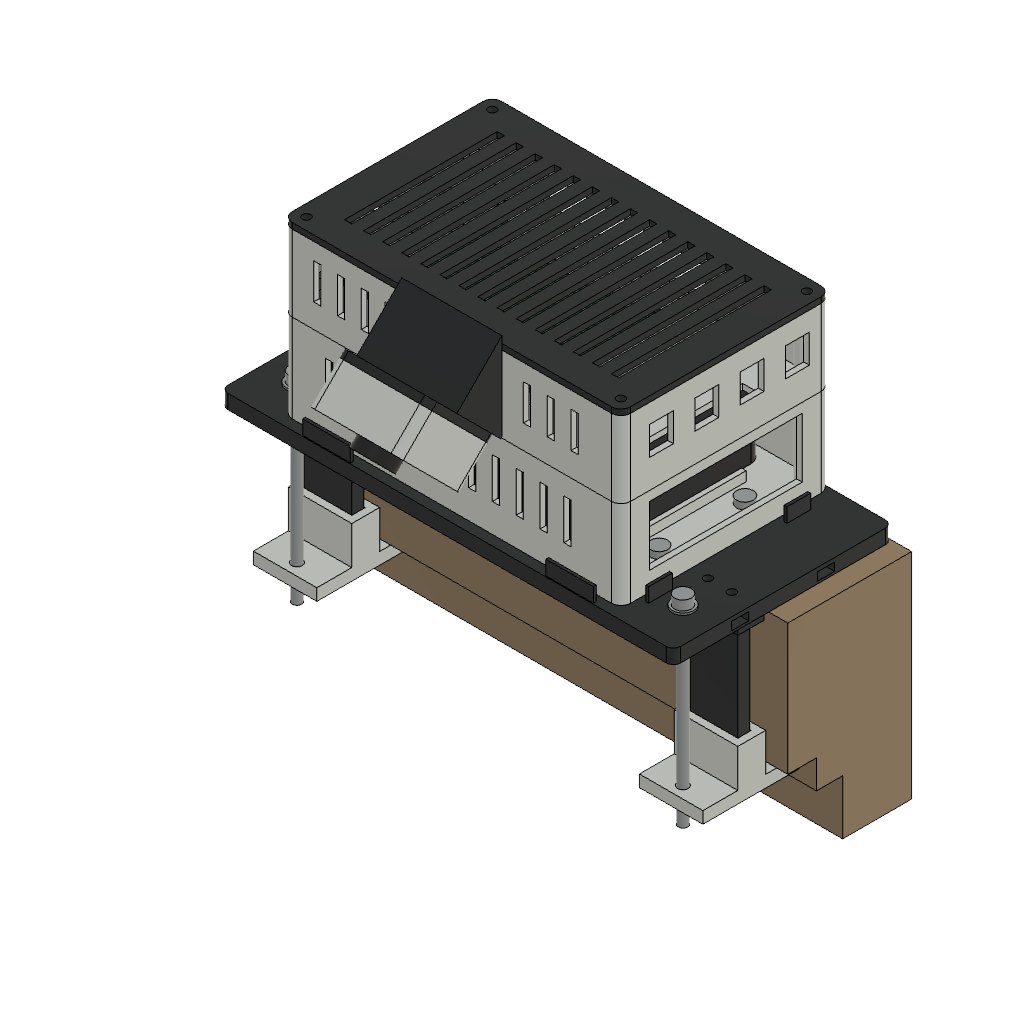
doorframe-camera-mounted-v3 (Autodesk Fusion 360 design; units mm, degrees)
part number: 2026-11-08-18-06-19-159
part number: 2026-11-08-18-06-19-927
part number: 2026-11-08-18-06-22-898
part number: 2026-11-08-18-06-26-282
part number: 2026-11-08-18-06-29-546
part number: 2026-11-08-18-06-30-123
part number: 2026-11-08-18-06-33-594
part number: 2026-11-08-18-06-36-129
part number: 2026-11-08-18-06-39-085
part number: 2026-11-08-18-06-42-850
part number: 2026-11-08-18-08-24-146
part number: 2026-11-08-20-22-30-806
part number: 2026-11-08-20-22-44-383
part number: 2026-11-08-20-22-46-977
part number: 2026-11-08-20-22-52-675
part number: 2026-11-08-20-22-55-258
part number: 2026-11-08-20-22-58-971
part number: 2026-11-08-20-22-59-876
part number: 2026-11-08-20-23-00-191
part number: 2026-11-08-20-26-10-020
Autodesk Fusion 360 part; units mm, degrees
(part 1 of 2)
sketch "Battery tray shell outline" plane through (0, 0, 0) normal (0, 0, 1) x (1, 0, 0) in component "01 Battery tray - PRINT"
  line L0 (4, 0) -> (138, 0)
  line L1 (142, 4) -> (142, 84)
  line L2 (138, 88) -> (4, 88)
  line L3 (0, 84) -> (0, 4)
  arc A0 (138, 0) -> (142, 4) centre (138, 4) ccw
  arc A1 (142, 84) -> (138, 88) centre (138, 84) ccw
  arc A2 (4, 88) -> (0, 84) centre (4, 84) ccw
  arc A3 (0, 4) -> (4, 0) centre (4, 4) ccw
extrude "Battery tray shell" add sketch "Battery tray shell outline" along normal blind 37 makes body 1 in component "01 Battery tray - PRINT"
ref_plane "WorkPlane1" through (0, 0, 2.4) normal (0, 0, 1) x (1, 0, 0) in component "01 Battery tray - PRINT"
sketch "Battery chamber outline" plane through (0, 0, 2.4) normal (0, 0, 1) x (1, 0, 0) in component "01 Battery tray - PRINT"
  line L0 (4, 2.4) -> (138, 2.4)
  line L1 (139.6, 4) -> (139.6, 84)
  line L2 (138, 85.6) -> (4, 85.6)
  line L3 (2.4, 84) -> (2.4, 4)
  arc A0 (138, 2.4) -> (139.6, 4) centre (138, 4) ccw
  arc A1 (139.6, 84) -> (138, 85.6) centre (138, 84) ccw
  arc A2 (4, 85.6) -> (2.4, 84) centre (4, 84) ccw
  arc A3 (2.4, 4) -> (4, 2.4) centre (4, 4) ccw
extrude "Battery chamber" cut sketch "Battery chamber outline" along normal blind 37 bodies 1 in component "01 Battery tray - PRINT"
ref_plane "WorkPlane2" through (0, 0, 2.4) normal (0, 0, 1) x (1, 0, 0) in component "01 Battery tray - PRINT"
sketch "Four corner screw pillars layout" plane through (0, 0, 2.4) normal (0, 0, 1) x (1, 0, 0) in component "01 Battery tray - PRINT"
  circle A0 centre (5, 5) radius 4
  circle A1 centre (137, 5) radius 4
  circle A2 centre (5, 83) radius 4
  circle A3 centre (137, 83) radius 4
extrude "Four corner screw pillars" add sketch "Four corner screw pillars layout" along normal blind 34.6 bodies 1 in component "01 Battery tray - PRINT"
ref_plane "WorkPlane3" through (0, 0, 22) normal (0, 0, 1) x (1, 0, 0) in component "01 Battery tray - PRINT"
sketch "M3 pilot holes - hand tap or plastic screws layout" plane through (0, 0, 22) normal (0, 0, 1) x (1, 0, 0) in component "01 Battery tray - PRINT"
  circle A0 centre (5, 5) radius 1.25
  circle A1 centre (137, 5) radius 1.25
  circle A2 centre (5, 83) radius 1.25
  circle A3 centre (137, 83) radius 1.25
extrude "M3 pilot holes - hand tap or plastic screws" cut sketch "M3 pilot holes - hand tap or plastic screws layout" along normal blind 16 bodies 1 in component "01 Battery tray - PRINT"
sketch "Battery strap slots - two 10 mm straps layout" plane through (0, 0, 0) normal (0, 0, 1) x (1, 0, 0) in component "01 Battery tray - PRINT"
  line L0 (41, 4) -> (53, 4)
  line L1 (53, 4) -> (53, 6.2)
  line L2 (53, 6.2) -> (41, 6.2)
  line L3 (41, 6.2) -> (41, 4)
  line L4 (41, 81.8) -> (53, 81.8)
  line L5 (53, 81.8) -> (53, 84)
  line L6 (53, 84) -> (41, 84)
  line L7 (41, 84) -> (41, 81.8)
  line L8 (94, 4) -> (106, 4)
  line L9 (106, 4) -> (106, 6.2)
  line L10 (106, 6.2) -> (94, 6.2)
  line L11 (94, 6.2) -> (94, 4)
  line L12 (94, 81.8) -> (106, 81.8)
  line L13 (106, 81.8) -> (106, 84)
  line L14 (106, 84) -> (94, 84)
  line L15 (94, 84) -> (94, 81.8)
extrude "Battery strap slots - two 10 mm straps" cut sketch "Battery strap slots - two 10 mm straps layout" along normal blind 3 bodies 1 in component "01 Battery tray - PRINT"
sketch "Rubber pad pockets - 20 x 10 mm layout" plane through (0, 0, 0) normal (0, 0, 1) x (1, 0, 0) in component "01 Battery tray - PRINT"
  line L0 (12, 7) -> (32, 7)
  line L1 (32, 7) -> (32, 17)
  line L2 (32, 17) -> (12, 17)
  line L3 (12, 17) -> (12, 7)
  line L4 (110, 7) -> (130, 7)
  line L5 (130, 7) -> (130, 17)
  line L6 (130, 17) -> (110, 17)
  line L7 (110, 17) -> (110, 7)
  line L8 (12, 71) -> (32, 71)
  line L9 (32, 71) -> (32, 81)
  line L10 (32, 81) -> (12, 81)
  line L11 (12, 81) -> (12, 71)
  line L12 (110, 71) -> (130, 71)
  line L13 (130, 71) -> (130, 81)
  line L14 (130, 81) -> (110, 81)
  line L15 (110, 81) -> (110, 71)
extrude "Rubber pad pockets - 20 x 10 mm" cut sketch "Rubber pad pockets - 20 x 10 mm layout" along normal blind 0.8 bodies 1 in component "01 Battery tray - PRINT"
ref_plane "WorkPlane4" through (0, 0, 12) normal (0, 0, 1) x (1, 0, 0) in component "01 Battery tray - PRINT"
sketch "Battery air slots layout" plane through (0, 0, 12) normal (0, 0, 1) x (1, 0, 0) in component "01 Battery tray - PRINT"
  line L0 (18, -1) -> (21, -1)
  line L1 (21, -1) -> (21, 3.2)
  line L2 (21, 3.2) -> (18, 3.2)
  line L3 (18, 3.2) -> (18, -1)
  line L4 (28, -1) -> (31, -1)
  line L5 (31, -1) -> (31, 3.2)
  line L6 (31, 3.2) -> (28, 3.2)
  line L7 (28, 3.2) -> (28, -1)
  line L8 (38, -1) -> (41, -1)
  line L9 (41, -1) -> (41, 3.2)
  line L10 (41, 3.2) -> (38, 3.2)
  line L11 (38, 3.2) -> (38, -1)
  line L12 (48, -1) -> (51, -1)
  line L13 (51, -1) -> (51, 3.2)
  line L14 (51, 3.2) -> (48, 3.2)
  line L15 (48, 3.2) -> (48, -1)
  line L16 (58, -1) -> (61, -1)
  line L17 (61, -1) -> (61, 3.2)
  line L18 (61, 3.2) -> (58, 3.2)
  line L19 (58, 3.2) -> (58, -1)
  line L20 (68, -1) -> (71, -1)
  line L21 (71, -1) -> (71, 3.2)
  line L22 (71, 3.2) -> (68, 3.2)
  line L23 (68, 3.2) -> (68, -1)
  line L24 (78, -1) -> (81, -1)
  line L25 (81, -1) -> (81, 3.2)
  line L26 (81, 3.2) -> (78, 3.2)
  line L27 (78, 3.2) -> (78, -1)
  line L28 (88, -1) -> (91, -1)
  line L29 (91, -1) -> (91, 3.2)
  line L30 (91, 3.2) -> (88, 3.2)
  line L31 (88, 3.2) -> (88, -1)
  line L32 (98, -1) -> (101, -1)
  line L33 (101, -1) -> (101, 3.2)
  line L34 (101, 3.2) -> (98, 3.2)
  line L35 (98, 3.2) -> (98, -1)
  line L36 (108, -1) -> (111, -1)
  line L37 (111, -1) -> (111, 3.2)
  line L38 (111, 3.2) -> (108, 3.2)
  line L39 (108, 3.2) -> (108, -1)
  line L40 (118, -1) -> (121, -1)
  line L41 (121, -1) -> (121, 3.2)
  line L42 (121, 3.2) -> (118, 3.2)
  line L43 (118, 3.2) -> (118, -1)
  line L44 (18, 84.8) -> (21, 84.8)
  line L45 (21, 84.8) -> (21, 89)
  line L46 (21, 89) -> (18, 89)
  line L47 (18, 89) -> (18, 84.8)
  line L48 (28, 84.8) -> (31, 84.8)
  line L49 (31, 84.8) -> (31, 89)
  line L50 (31, 89) -> (28, 89)
  line L51 (28, 89) -> (28, 84.8)
  line L52 (38, 84.8) -> (41, 84.8)
  line L53 (41, 84.8) -> (41, 89)
  line L54 (41, 89) -> (38, 89)
  line L55 (38, 89) -> (38, 84.8)
  line L56 (48, 84.8) -> (51, 84.8)
  line L57 (51, 84.8) -> (51, 89)
  line L58 (51, 89) -> (48, 89)
  line L59 (48, 89) -> (48, 84.8)
  line L60 (58, 84.8) -> (61, 84.8)
  line L61 (61, 84.8) -> (61, 89)
  line L62 (61, 89) -> (58, 89)
  line L63 (58, 89) -> (58, 84.8)
  line L64 (68, 84.8) -> (71, 84.8)
  line L65 (71, 84.8) -> (71, 89)
  line L66 (71, 89) -> (68, 89)
  line L67 (68, 89) -> (68, 84.8)
  line L68 (78, 84.8) -> (81, 84.8)
  line L69 (81, 84.8) -> (81, 89)
  line L70 (81, 89) -> (78, 89)
  line L71 (78, 89) -> (78, 84.8)
  line L72 (88, 84.8) -> (91, 84.8)
  line L73 (91, 84.8) -> (91, 89)
  line L74 (91, 89) -> (88, 89)
  line L75 (88, 89) -> (88, 84.8)
  line L76 (98, 84.8) -> (101, 84.8)
  line L77 (101, 84.8) -> (101, 89)
  line L78 (101, 89) -> (98, 89)
  line L79 (98, 89) -> (98, 84.8)
  line L80 (108, 84.8) -> (111, 84.8)
  line L81 (111, 84.8) -> (111, 89)
  line L82 (111, 89) -> (108, 89)
  line L83 (108, 89) -> (108, 84.8)
  line L84 (118, 84.8) -> (121, 84.8)
  line L85 (121, 84.8) -> (121, 89)
  line L86 (121, 89) -> (118, 89)
  line L87 (118, 89) -> (118, 84.8)
extrude "Battery air slots" cut sketch "Battery air slots layout" along normal blind 17 bodies 1 in component "01 Battery tray - PRINT"
ref_plane "WorkPlane5" through (0, 0, 8) normal (0, 0, 1) x (1, 0, 0) in component "01 Battery tray - PRINT"
sketch "Battery connector access layout" plane through (0, 0, 8) normal (0, 0, 1) x (1, 0, 0) in component "01 Battery tray - PRINT"
  line L0 (139, 12) -> (143, 12)
  line L1 (143, 12) -> (143, 76)
  line L2 (143, 76) -> (139, 76)
  line L3 (139, 76) -> (139, 12)
extrude "Battery connector access" cut sketch "Battery connector access layout" along normal blind 25 bodies 1 in component "01 Battery tray - PRINT"
ref_plane "WorkPlane6" through (0, 0, 2.4) normal (0, 0, 1) x (1, 0, 0) in component "01 Battery tray - PRINT"
sketch "Battery end stop outline" plane through (0, 0, 2.4) normal (0, 0, 1) x (1, 0, 0) in component "01 Battery tray - PRINT"
  line L0 (3, 18) -> (5, 18)
  line L1 (5, 18) -> (5, 70)
  line L2 (5, 70) -> (3, 70)
  line L3 (3, 70) -> (3, 18)
extrude "Battery end stop" add sketch "Battery end stop outline" along normal blind 4 bodies 1 in component "01 Battery tray - PRINT"
ref_plane "WorkPlane7" through (0, 0, 2.4) normal (0, 0, 1) x (1, 0, 0) in component "01 Battery tray - PRINT"
sketch "Battery cable-side stop outline" plane through (0, 0, 2.4) normal (0, 0, 1) x (1, 0, 0) in component "01 Battery tray - PRINT"
  line L0 (122.5, 18) -> (124.5, 18)
  line L1 (124.5, 18) -> (124.5, 70)
  line L2 (124.5, 70) -> (122.5, 70)
  line L3 (122.5, 70) -> (122.5, 18)
extrude "Battery cable-side stop" add sketch "Battery cable-side stop outline" along normal blind 4 bodies 1 in component "01 Battery tray - PRINT"
sketch "M4 mounting interface layout" plane through (0, 0, 0) normal (0, 0, 1) x (1, 0, 0) in component "01 Battery tray - PRINT"
  circle A0 centre (132, 26) radius 2.25
  circle A1 centre (132, 62) radius 2.25
extrude "M4 mounting interface" cut sketch "M4 mounting interface layout" along normal blind 3 bodies 1 in component "01 Battery tray - PRINT"
ref_plane "WorkPlane1" through (0, 0, 37) normal (0, 0, 1) x (1, 0, 0) in component "02 Pi tray and upper shell - PRINT"
sketch "Upper shell outline" plane through (0, 0, 37) normal (0, 0, 1) x (1, 0, 0) in component "02 Pi tray and upper shell - PRINT"
  line L0 (4, 0) -> (138, 0)
  line L1 (142, 4) -> (142, 84)
  line L2 (138, 88) -> (4, 88)
  line L3 (0, 84) -> (0, 4)
  arc A0 (138, 0) -> (142, 4) centre (138, 4) ccw
  arc A1 (142, 84) -> (138, 88) centre (138, 84) ccw
  arc A2 (4, 88) -> (0, 84) centre (4, 84) ccw
  arc A3 (0, 4) -> (4, 0) centre (4, 4) ccw
extrude "Upper shell" add sketch "Upper shell outline" along normal blind 32 separate body makes body 2 in component "02 Pi tray and upper shell - PRINT"
ref_plane "WorkPlane2" through (0, 0, 39.4) normal (0, 0, 1) x (1, 0, 0) in component "02 Pi tray and upper shell - PRINT"
sketch "Pi chamber outline" plane through (0, 0, 39.4) normal (0, 0, 1) x (1, 0, 0) in component "02 Pi tray and upper shell - PRINT"
  line L0 (4, 2.4) -> (138, 2.4)
  line L1 (139.6, 4) -> (139.6, 84)
  line L2 (138, 85.6) -> (4, 85.6)
  line L3 (2.4, 84) -> (2.4, 4)
  arc A0 (138, 2.4) -> (139.6, 4) centre (138, 4) ccw
  arc A1 (139.6, 84) -> (138, 85.6) centre (138, 84) ccw
  arc A2 (4, 85.6) -> (2.4, 84) centre (4, 84) ccw
  arc A3 (2.4, 4) -> (4, 2.4) centre (4, 4) ccw
extrude "Pi chamber" cut sketch "Pi chamber outline" along normal blind 32 bodies 2 in component "02 Pi tray and upper shell - PRINT"
ref_plane "WorkPlane3" through (0, 0, 39.4) normal (0, 0, 1) x (1, 0, 0) in component "02 Pi tray and upper shell - PRINT"
sketch "Upper corner pillars layout" plane through (0, 0, 39.4) normal (0, 0, 1) x (1, 0, 0) in component "02 Pi tray and upper shell - PRINT"
  circle A0 centre (5, 5) radius 4
  circle A1 centre (137, 5) radius 4
  circle A2 centre (5, 83) radius 4
  circle A3 centre (137, 83) radius 4
extrude "Upper corner pillars" add sketch "Upper corner pillars layout" along normal blind 29.6 bodies 2 in component "02 Pi tray and upper shell - PRINT"
ref_plane "WorkPlane4" through (0, 0, 36.8) normal (0, 0, 1) x (1, 0, 0) in component "02 Pi tray and upper shell - PRINT"
sketch "M3 long-screw clearance layout" plane through (0, 0, 36.8) normal (0, 0, 1) x (1, 0, 0) in component "02 Pi tray and upper shell - PRINT"
  circle A0 centre (5, 5) radius 1.7
  circle A1 centre (137, 5) radius 1.7
  circle A2 centre (5, 83) radius 1.7
  circle A3 centre (137, 83) radius 1.7
extrude "M3 long-screw clearance" cut sketch "M3 long-screw clearance layout" along normal blind 33 bodies 2 in component "02 Pi tray and upper shell - PRINT"
ref_plane "WorkPlane5" through (0, 0, 39.4) normal (0, 0, 1) x (1, 0, 0) in component "02 Pi tray and upper shell - PRINT"
sketch "Pi4 mounting standoffs - 58 x 49 mm layout" plane through (0, 0, 39.4) normal (0, 0, 1) x (1, 0, 0) in component "02 Pi tray and upper shell - PRINT"
  circle A0 centre (87.5, 67.5) radius 3
  circle A1 centre (29.5, 67.5) radius 3
  circle A2 centre (87.5, 18.5) radius 3
  circle A3 centre (29.5, 18.5) radius 3
extrude "Pi4 mounting standoffs - 58 x 49 mm" add sketch "Pi4 mounting standoffs - 58 x 49 mm layout" along normal blind 5 bodies 2 in component "02 Pi tray and upper shell - PRINT"
ref_plane "WorkPlane6" through (0, 0, 38) normal (0, 0, 1) x (1, 0, 0) in component "02 Pi tray and upper shell - PRINT"
sketch "M2.5 Pi screw pilot holes layout" plane through (0, 0, 38) normal (0, 0, 1) x (1, 0, 0) in component "02 Pi tray and upper shell - PRINT"
  circle A0 centre (87.5, 67.5) radius 1.05
  circle A1 centre (29.5, 67.5) radius 1.05
  circle A2 centre (87.5, 18.5) radius 1.05
  circle A3 centre (29.5, 18.5) radius 1.05
extrude "M2.5 Pi screw pilot holes" cut sketch "M2.5 Pi screw pilot holes layout" along normal blind 7.4 bodies 2 in component "02 Pi tray and upper shell - PRINT"
ref_plane "WorkPlane7" through (0, 0, 43.6) normal (0, 0, 1) x (1, 0, 0) in component "02 Pi tray and upper shell - PRINT"
sketch "USB and Ethernet access layout" plane through (0, 0, 43.6) normal (0, 0, 1) x (1, 0, 0) in component "02 Pi tray and upper shell - PRINT"
  line L0 (-1, 12) -> (3.2, 12)
  line L1 (3.2, 12) -> (3.2, 76)
  line L2 (3.2, 76) -> (-1, 76)
  line L3 (-1, 76) -> (-1, 12)
extrude "USB and Ethernet access" cut sketch "USB and Ethernet access layout" along normal blind 20 bodies 2 in component "02 Pi tray and upper shell - PRINT"
ref_plane "WorkPlane8" through (0, 0, 43.5) normal (0, 0, 1) x (1, 0, 0) in component "02 Pi tray and upper shell - PRINT"
sketch "USB-C and micro-HDMI access layout" plane through (0, 0, 43.5) normal (0, 0, 1) x (1, 0, 0) in component "02 Pi tray and upper shell - PRINT"
  line L0 (24, 84.8) -> (92, 84.8)
  line L1 (92, 84.8) -> (92, 89)
  line L2 (92, 89) -> (24, 89)
  line L3 (24, 89) -> (24, 84.8)
extrude "USB-C and micro-HDMI access" cut sketch "USB-C and micro-HDMI access layout" along normal blind 13 bodies 2 in component "02 Pi tray and upper shell - PRINT"
ref_plane "WorkPlane9" through (0, 0, 36.9) normal (0, 0, 1) x (1, 0, 0) in component "02 Pi tray and upper shell - PRINT"
sketch "Power and ribbon cable passage layout" plane through (0, 0, 36.9) normal (0, 0, 1) x (1, 0, 0) in component "02 Pi tray and upper shell - PRINT"
  line L0 (125, 20) -> (135, 20)
  line L1 (135, 20) -> (135, 68)
  line L2 (135, 68) -> (125, 68)
  line L3 (125, 68) -> (125, 20)
extrude "Power and ribbon cable passage" cut sketch "Power and ribbon cable passage layout" along normal blind 3 bodies 2 in component "02 Pi tray and upper shell - PRINT"
ref_plane "WorkPlane10" through (0, 0, 47) normal (0, 0, 1) x (1, 0, 0) in component "02 Pi tray and upper shell - PRINT"
sketch "Ventilation front layout" plane through (0, 0, 47) normal (0, 0, 1) x (1, 0, 0) in component "02 Pi tray and upper shell - PRINT"
  line L0 (13, -1) -> (16, -1)
  line L1 (16, -1) -> (16, 3.2)
  line L2 (16, 3.2) -> (13, 3.2)
  line L3 (13, 3.2) -> (13, -1)
  line L4 (23, -1) -> (26, -1)
  line L5 (26, -1) -> (26, 3.2)
  line L6 (26, 3.2) -> (23, 3.2)
  line L7 (23, 3.2) -> (23, -1)
  line L8 (33, -1) -> (36, -1)
  line L9 (36, -1) -> (36, 3.2)
  line L10 (36, 3.2) -> (33, 3.2)
  line L11 (33, 3.2) -> (33, -1)
  line L12 (43, -1) -> (46, -1)
  line L13 (46, -1) -> (46, 3.2)
  line L14 (46, 3.2) -> (43, 3.2)
  line L15 (43, 3.2) -> (43, -1)
  line L16 (101, -1) -> (104, -1)
  line L17 (104, -1) -> (104, 3.2)
  line L18 (104, 3.2) -> (101, 3.2)
  line L19 (101, 3.2) -> (101, -1)
  line L20 (111, -1) -> (114, -1)
  line L21 (114, -1) -> (114, 3.2)
  line L22 (114, 3.2) -> (111, 3.2)
  line L23 (111, 3.2) -> (111, -1)
  line L24 (121, -1) -> (124, -1)
  line L25 (124, -1) -> (124, 3.2)
  line L26 (124, 3.2) -> (121, 3.2)
  line L27 (121, 3.2) -> (121, -1)
extrude "Ventilation front" cut sketch "Ventilation front layout" along normal blind 15 bodies 2 in component "02 Pi tray and upper shell - PRINT"
ref_plane "WorkPlane11" through (0, 0, 49) normal (0, 0, 1) x (1, 0, 0) in component "02 Pi tray and upper shell - PRINT"
sketch "Ventilation right layout" plane through (0, 0, 49) normal (0, 0, 1) x (1, 0, 0) in component "02 Pi tray and upper shell - PRINT"
  line L0 (139, 12) -> (143, 12)
  line L1 (143, 12) -> (143, 22)
  line L2 (143, 22) -> (139, 22)
  line L3 (139, 22) -> (139, 12)
  line L4 (139, 31) -> (143, 31)
  line L5 (143, 31) -> (143, 41)
  line L6 (143, 41) -> (139, 41)
  line L7 (139, 41) -> (139, 31)
  line L8 (139, 50) -> (143, 50)
  line L9 (143, 50) -> (143, 60)
  line L10 (143, 60) -> (139, 60)
  line L11 (139, 60) -> (139, 50)
  line L12 (139, 69) -> (143, 69)
  line L13 (143, 69) -> (143, 79)
  line L14 (143, 79) -> (139, 79)
  line L15 (139, 79) -> (139, 69)
extrude "Ventilation right" cut sketch "Ventilation right layout" along normal blind 12 bodies 2 in component "02 Pi tray and upper shell - PRINT"
sketch "Camera bracket M3 clearance layout" plane through (0, 0, 0) normal (0, 1, 0) x (1, 0, 0) in component "02 Pi tray and upper shell - PRINT"
  circle A0 centre (59, -49) radius 1.7
  circle A1 centre (83, -49) radius 1.7
  circle A2 centre (59, -61) radius 1.7
  circle A3 centre (83, -61) radius 1.7
extrude "Camera bracket M3 clearance" cut sketch "Camera bracket M3 clearance layout" along normal blind 3 bodies 2 in component "02 Pi tray and upper shell - PRINT"
ref_plane "WorkPlane1" through (0, 0, 69) normal (0, 0, 1) x (1, 0, 0) in component "03 Vented lid - PRINT"
sketch "Lid outline" plane through (0, 0, 69) normal (0, 0, 1) x (1, 0, 0) in component "03 Vented lid - PRINT"
  line L0 (4, 0) -> (138, 0)
  line L1 (142, 4) -> (142, 84)
  line L2 (138, 88) -> (4, 88)
  line L3 (0, 84) -> (0, 4)
  arc A0 (138, 0) -> (142, 4) centre (138, 4) ccw
  arc A1 (142, 84) -> (138, 88) centre (138, 84) ccw
  arc A2 (4, 88) -> (0, 84) centre (4, 84) ccw
  arc A3 (0, 4) -> (4, 0) centre (4, 4) ccw
extrude "Lid" add sketch "Lid outline" along normal blind 2.4 separate body makes body 3 in component "03 Vented lid - PRINT"
ref_plane "WorkPlane2" through (0, 0, 68.9) normal (0, 0, 1) x (1, 0, 0) in component "03 Vented lid - PRINT"
sketch "M3 lid clearance layout" plane through (0, 0, 68.9) normal (0, 0, 1) x (1, 0, 0) in component "03 Vented lid - PRINT"
  circle A0 centre (5, 5) radius 1.7
  circle A1 centre (137, 5) radius 1.7
  circle A2 centre (5, 83) radius 1.7
  circle A3 centre (137, 83) radius 1.7
extrude "M3 lid clearance" cut sketch "M3 lid clearance layout" along normal blind 3 bodies 3 in component "03 Vented lid - PRINT"
ref_plane "WorkPlane3" through (0, 0, 68.9) normal (0, 0, 1) x (1, 0, 0) in component "03 Vented lid - PRINT"
sketch "Lid ventilation layout" plane through (0, 0, 68.9) normal (0, 0, 1) x (1, 0, 0) in component "03 Vented lid - PRINT"
  line L0 (14, 12) -> (17, 12)
  line L1 (17, 12) -> (17, 76)
  line L2 (17, 76) -> (14, 76)
  line L3 (14, 76) -> (14, 12)
  line L4 (22, 12) -> (25, 12)
  line L5 (25, 12) -> (25, 76)
  line L6 (25, 76) -> (22, 76)
  line L7 (22, 76) -> (22, 12)
  line L8 (30, 12) -> (33, 12)
  line L9 (33, 12) -> (33, 76)
  line L10 (33, 76) -> (30, 76)
  line L11 (30, 76) -> (30, 12)
  line L12 (38, 12) -> (41, 12)
  line L13 (41, 12) -> (41, 76)
  line L14 (41, 76) -> (38, 76)
  line L15 (38, 76) -> (38, 12)
  line L16 (46, 12) -> (49, 12)
  line L17 (49, 12) -> (49, 76)
  line L18 (49, 76) -> (46, 76)
  line L19 (46, 76) -> (46, 12)
  line L20 (54, 12) -> (57, 12)
  line L21 (57, 12) -> (57, 76)
  line L22 (57, 76) -> (54, 76)
  line L23 (54, 76) -> (54, 12)
  line L24 (62, 12) -> (65, 12)
  line L25 (65, 12) -> (65, 76)
  line L26 (65, 76) -> (62, 76)
  line L27 (62, 76) -> (62, 12)
  line L28 (70, 12) -> (73, 12)
  line L29 (73, 12) -> (73, 76)
  line L30 (73, 76) -> (70, 76)
  line L31 (70, 76) -> (70, 12)
  line L32 (78, 12) -> (81, 12)
  line L33 (81, 12) -> (81, 76)
  line L34 (81, 76) -> (78, 76)
  line L35 (78, 76) -> (78, 12)
  line L36 (86, 12) -> (89, 12)
  line L37 (89, 12) -> (89, 76)
  line L38 (89, 76) -> (86, 76)
  line L39 (86, 76) -> (86, 12)
  line L40 (94, 12) -> (97, 12)
  line L41 (97, 12) -> (97, 76)
  line L42 (97, 76) -> (94, 76)
  line L43 (94, 76) -> (94, 12)
  line L44 (102, 12) -> (105, 12)
  line L45 (105, 12) -> (105, 76)
  line L46 (105, 76) -> (102, 76)
  line L47 (102, 76) -> (102, 12)
  line L48 (110, 12) -> (113, 12)
  line L49 (113, 12) -> (113, 76)
  line L50 (113, 76) -> (110, 76)
  line L51 (110, 76) -> (110, 12)
  line L52 (118, 12) -> (121, 12)
  line L53 (121, 12) -> (121, 76)
  line L54 (121, 76) -> (118, 76)
  line L55 (118, 76) -> (118, 12)
  line L56 (126, 12) -> (129, 12)
  line L57 (129, 12) -> (129, 76)
  line L58 (129, 76) -> (126, 76)
  line L59 (126, 76) -> (126, 12)
extrude "Lid ventilation" cut sketch "Lid ventilation layout" along normal blind 3 bodies 3 in component "03 Vented lid - PRINT"
ref_plane "WorkPlane4" through (0, 0, 66.5) normal (0, 0, 1) x (1, 0, 0) in component "03 Vented lid - PRINT"
sketch "Lid alignment tab 1 outline" plane through (0, 0, 66.5) normal (0, 0, 1) x (1, 0, 0) in component "03 Vented lid - PRINT"
  line L0 (15, 2.8) -> (30, 2.8)
  line L1 (30, 2.8) -> (30, 4)
  line L2 (30, 4) -> (15, 4)
  line L3 (15, 4) -> (15, 2.8)
extrude "Lid alignment tab 1" add sketch "Lid alignment tab 1 outline" along normal blind 2.5 bodies 3 in component "03 Vented lid - PRINT"
ref_plane "WorkPlane5" through (0, 0, 66.5) normal (0, 0, 1) x (1, 0, 0) in component "03 Vented lid - PRINT"
sketch "Lid alignment tab 2 outline" plane through (0, 0, 66.5) normal (0, 0, 1) x (1, 0, 0) in component "03 Vented lid - PRINT"
  line L0 (111, 2.8) -> (126, 2.8)
  line L1 (126, 2.8) -> (126, 4)
  line L2 (126, 4) -> (111, 4)
  line L3 (111, 4) -> (111, 2.8)
extrude "Lid alignment tab 2" add sketch "Lid alignment tab 2 outline" along normal blind 2.5 bodies 3 in component "03 Vented lid - PRINT"
ref_plane "WorkPlane6" through (0, 0, 66.5) normal (0, 0, 1) x (1, 0, 0) in component "03 Vented lid - PRINT"
sketch "Lid alignment tab 3 outline" plane through (0, 0, 66.5) normal (0, 0, 1) x (1, 0, 0) in component "03 Vented lid - PRINT"
  line L0 (15, 84) -> (30, 84)
  line L1 (30, 84) -> (30, 85.2)
  line L2 (30, 85.2) -> (15, 85.2)
  line L3 (15, 85.2) -> (15, 84)
extrude "Lid alignment tab 3" add sketch "Lid alignment tab 3 outline" along normal blind 2.5 bodies 3 in component "03 Vented lid - PRINT"
ref_plane "WorkPlane7" through (0, 0, 66.5) normal (0, 0, 1) x (1, 0, 0) in component "03 Vented lid - PRINT"
sketch "Lid alignment tab 4 outline" plane through (0, 0, 66.5) normal (0, 0, 1) x (1, 0, 0) in component "03 Vented lid - PRINT"
  line L0 (111, 84) -> (126, 84)
  line L1 (126, 84) -> (126, 85.2)
  line L2 (126, 85.2) -> (111, 85.2)
  line L3 (111, 85.2) -> (111, 84)
extrude "Lid alignment tab 4" add sketch "Lid alignment tab 4 outline" along normal blind 2.5 bodies 3 in component "03 Vented lid - PRINT"
ref_plane "WorkPlane1" through (0, 0, 4.4) normal (0, 0, 1) x (1, 0, 0) in component "REFERENCE - INIU P51L-E2 115 x 73 x 29 mm"
sketch "INIU envelope - check supplied cable position outline" plane through (0, 0, 4.4) normal (0, 0, 1) x (1, 0, 0) in component "REFERENCE - INIU P51L-E2 115 x 73 x 29 mm"
  line L0 (11, 7.5) -> (116, 7.5)
  line L1 (121, 12.5) -> (121, 75.5)
  line L2 (116, 80.5) -> (11, 80.5)
  line L3 (6, 75.5) -> (6, 12.5)
  arc A0 (116, 7.5) -> (121, 12.5) centre (116, 12.5) ccw
  arc A1 (121, 75.5) -> (116, 80.5) centre (116, 75.5) ccw
  arc A2 (11, 80.5) -> (6, 75.5) centre (11, 75.5) ccw
  arc A3 (6, 12.5) -> (11, 7.5) centre (11, 12.5) ccw
extrude "INIU envelope - check supplied cable position" add sketch "INIU envelope - check supplied cable position outline" along normal blind 29 separate body makes body 4 in component "REFERENCE - INIU P51L-E2 115 x 73 x 29 mm"
ref_plane "WorkPlane1" through (0, 0, 44.4) normal (0, 0, 1) x (1, 0, 0) in component "REFERENCE - Raspberry Pi4 rotated ports"
sketch "Pi PCB 85 x 56 x 1.6 outline" plane through (0, 0, 44.4) normal (0, 0, 1) x (1, 0, 0) in component "REFERENCE - Raspberry Pi4 rotated ports"
  line L0 (9, 15) -> (88, 15)
  line L1 (91, 18) -> (91, 68)
  line L2 (88, 71) -> (9, 71)
  line L3 (6, 68) -> (6, 18)
  arc A0 (88, 15) -> (91, 18) centre (88, 18) ccw
  arc A1 (91, 68) -> (88, 71) centre (88, 68) ccw
  arc A2 (9, 71) -> (6, 68) centre (9, 68) ccw
  arc A3 (6, 18) -> (9, 15) centre (9, 18) ccw
extrude "Pi PCB 85 x 56 x 1.6" add sketch "Pi PCB 85 x 56 x 1.6 outline" along normal blind 1.6 separate body makes body 5 in component "REFERENCE - Raspberry Pi4 rotated ports"
ref_plane "WorkPlane2" through (0, 0, 44.3) normal (0, 0, 1) x (1, 0, 0) in component "REFERENCE - Raspberry Pi4 rotated ports"
sketch "Pi mounting holes layout" plane through (0, 0, 44.3) normal (0, 0, 1) x (1, 0, 0) in component "REFERENCE - Raspberry Pi4 rotated ports"
  circle A0 centre (87.5, 67.5) radius 1.375
  circle A1 centre (29.5, 67.5) radius 1.375
  circle A2 centre (87.5, 18.5) radius 1.375
  circle A3 centre (29.5, 18.5) radius 1.375
extrude "Pi mounting holes" cut sketch "Pi mounting holes layout" along normal blind 2 bodies 5 in component "REFERENCE - Raspberry Pi4 rotated ports"
ref_plane "WorkPlane3" through (0, 0, 46) normal (0, 0, 1) x (1, 0, 0) in component "REFERENCE - Raspberry Pi4 rotated ports"
sketch "USB3 outline" plane through (0, 0, 46) normal (0, 0, 1) x (1, 0, 0) in component "REFERENCE - Raspberry Pi4 rotated ports"
  line L0 (3, 55.4) -> (20.5, 55.4)
  line L1 (20.5, 55.4) -> (20.5, 68.6)
  line L2 (20.5, 68.6) -> (3, 68.6)
  line L3 (3, 68.6) -> (3, 55.4)
extrude "USB3" add sketch "USB3 outline" along normal blind 16 separate body makes body 6 in component "REFERENCE - Raspberry Pi4 rotated ports"
ref_plane "WorkPlane4" through (0, 0, 46) normal (0, 0, 1) x (1, 0, 0) in component "REFERENCE - Raspberry Pi4 rotated ports"
sketch "USB2 outline" plane through (0, 0, 46) normal (0, 0, 1) x (1, 0, 0) in component "REFERENCE - Raspberry Pi4 rotated ports"
  line L0 (3, 37.4) -> (20.5, 37.4)
  line L1 (20.5, 37.4) -> (20.5, 50.6)
  line L2 (20.5, 50.6) -> (3, 50.6)
  line L3 (3, 50.6) -> (3, 37.4)
extrude "USB2" add sketch "USB2 outline" along normal blind 16 separate body makes body 7 in component "REFERENCE - Raspberry Pi4 rotated ports"
ref_plane "WorkPlane5" through (0, 0, 46) normal (0, 0, 1) x (1, 0, 0) in component "REFERENCE - Raspberry Pi4 rotated ports"
sketch "Ethernet outline" plane through (0, 0, 46) normal (0, 0, 1) x (1, 0, 0) in component "REFERENCE - Raspberry Pi4 rotated ports"
  line L0 (3, 17.5) -> (24.5, 17.5)
  line L1 (24.5, 17.5) -> (24.5, 33.5)
  line L2 (24.5, 33.5) -> (3, 33.5)
  line L3 (3, 33.5) -> (3, 17.5)
extrude "Ethernet" add sketch "Ethernet outline" along normal blind 13.5 separate body makes body 8 in component "REFERENCE - Raspberry Pi4 rotated ports"
ref_plane "WorkPlane6" through (0, 0, 46) normal (0, 0, 1) x (1, 0, 0) in component "REFERENCE - Raspberry Pi4 rotated ports"
sketch "USB-C outline" plane through (0, 0, 46) normal (0, 0, 1) x (1, 0, 0) in component "REFERENCE - Raspberry Pi4 rotated ports"
  line L0 (73.5, 64) -> (86.1, 64)
  line L1 (86.1, 64) -> (86.1, 72)
  line L2 (86.1, 72) -> (73.5, 72)
  line L3 (73.5, 72) -> (73.5, 64)
extrude "USB-C" add sketch "USB-C outline" along normal blind 3.2 separate body makes body 9 in component "REFERENCE - Raspberry Pi4 rotated ports"
ref_plane "WorkPlane7" through (0, 0, 46) normal (0, 0, 1) x (1, 0, 0) in component "REFERENCE - Raspberry Pi4 rotated ports"
sketch "HDMI0 outline" plane through (0, 0, 46) normal (0, 0, 1) x (1, 0, 0) in component "REFERENCE - Raspberry Pi4 rotated ports"
  line L0 (60.5, 64) -> (69.5, 64)
  line L1 (69.5, 64) -> (69.5, 72)
  line L2 (69.5, 72) -> (60.5, 72)
  line L3 (60.5, 72) -> (60.5, 64)
extrude "HDMI0" add sketch "HDMI0 outline" along normal blind 3 separate body makes body 10 in component "REFERENCE - Raspberry Pi4 rotated ports"
ref_plane "WorkPlane8" through (0, 0, 46) normal (0, 0, 1) x (1, 0, 0) in component "REFERENCE - Raspberry Pi4 rotated ports"
sketch "HDMI1 outline" plane through (0, 0, 46) normal (0, 0, 1) x (1, 0, 0) in component "REFERENCE - Raspberry Pi4 rotated ports"
  line L0 (47, 64) -> (56, 64)
  line L1 (56, 64) -> (56, 72)
  line L2 (56, 72) -> (47, 72)
  line L3 (47, 72) -> (47, 64)
extrude "HDMI1" add sketch "HDMI1 outline" along normal blind 3 separate body makes body 11 in component "REFERENCE - Raspberry Pi4 rotated ports"
ref_plane "WorkPlane9" through (0, 0, 46) normal (0, 0, 1) x (1, 0, 0) in component "REFERENCE - Raspberry Pi4 rotated ports"
sketch "Audio outline" plane through (0, 0, 46) normal (0, 0, 1) x (1, 0, 0) in component "REFERENCE - Raspberry Pi4 rotated ports"
  line L0 (33.5, 58) -> (40.5, 58)
  line L1 (40.5, 58) -> (40.5, 72)
  line L2 (40.5, 72) -> (33.5, 72)
  line L3 (33.5, 72) -> (33.5, 58)
extrude "Audio" add sketch "Audio outline" along normal blind 6 separate body makes body 12 in component "REFERENCE - Raspberry Pi4 rotated ports"
ref_plane "WorkPlane1" through (0, 0, -2.2) normal (0, 0, 1) x (1, 0, 0) in component "REFERENCE - four 20 x 10 x 3 mm rubber pads"
sketch "Rubber pad 1 outline" plane through (0, 0, -2.2) normal (0, 0, 1) x (1, 0, 0) in component "REFERENCE - four 20 x 10 x 3 mm rubber pads"
  line L0 (13, 7) -> (31, 7)
  line L1 (32, 8) -> (32, 16)
  line L2 (31, 17) -> (13, 17)
  line L3 (12, 16) -> (12, 8)
  arc A0 (31, 7) -> (32, 8) centre (31, 8) ccw
  arc A1 (32, 16) -> (31, 17) centre (31, 16) ccw
  arc A2 (13, 17) -> (12, 16) centre (13, 16) ccw
  arc A3 (12, 8) -> (13, 7) centre (13, 8) ccw
extrude "Rubber pad 1" add sketch "Rubber pad 1 outline" along normal blind 3 separate body makes body 13 in component "REFERENCE - four 20 x 10 x 3 mm rubber pads"
ref_plane "WorkPlane2" through (0, 0, -2.2) normal (0, 0, 1) x (1, 0, 0) in component "REFERENCE - four 20 x 10 x 3 mm rubber pads"
sketch "Rubber pad 2 outline" plane through (0, 0, -2.2) normal (0, 0, 1) x (1, 0, 0) in component "REFERENCE - four 20 x 10 x 3 mm rubber pads"
  line L0 (111, 7) -> (129, 7)
  line L1 (130, 8) -> (130, 16)
  line L2 (129, 17) -> (111, 17)
  line L3 (110, 16) -> (110, 8)
  arc A0 (129, 7) -> (130, 8) centre (129, 8) ccw
  arc A1 (130, 16) -> (129, 17) centre (129, 16) ccw
  arc A2 (111, 17) -> (110, 16) centre (111, 16) ccw
  arc A3 (110, 8) -> (111, 7) centre (111, 8) ccw
extrude "Rubber pad 2" add sketch "Rubber pad 2 outline" along normal blind 3 separate body makes body 14 in component "REFERENCE - four 20 x 10 x 3 mm rubber pads"
ref_plane "WorkPlane3" through (0, 0, -2.2) normal (0, 0, 1) x (1, 0, 0) in component "REFERENCE - four 20 x 10 x 3 mm rubber pads"
sketch "Rubber pad 3 outline" plane through (0, 0, -2.2) normal (0, 0, 1) x (1, 0, 0) in component "REFERENCE - four 20 x 10 x 3 mm rubber pads"
  line L0 (13, 71) -> (31, 71)
  line L1 (32, 72) -> (32, 80)
  line L2 (31, 81) -> (13, 81)
  line L3 (12, 80) -> (12, 72)
  arc A0 (31, 71) -> (32, 72) centre (31, 72) ccw
  arc A1 (32, 80) -> (31, 81) centre (31, 80) ccw
  arc A2 (13, 81) -> (12, 80) centre (13, 80) ccw
  arc A3 (12, 72) -> (13, 71) centre (13, 72) ccw
extrude "Rubber pad 3" add sketch "Rubber pad 3 outline" along normal blind 3 separate body makes body 15 in component "REFERENCE - four 20 x 10 x 3 mm rubber pads"
ref_plane "WorkPlane4" through (0, 0, -2.2) normal (0, 0, 1) x (1, 0, 0) in component "REFERENCE - four 20 x 10 x 3 mm rubber pads"
sketch "Rubber pad 4 outline" plane through (0, 0, -2.2) normal (0, 0, 1) x (1, 0, 0) in component "REFERENCE - four 20 x 10 x 3 mm rubber pads"
  line L0 (111, 71) -> (129, 71)
  line L1 (130, 72) -> (130, 80)
  line L2 (129, 81) -> (111, 81)
  line L3 (110, 80) -> (110, 72)
  arc A0 (129, 71) -> (130, 72) centre (129, 72) ccw
  arc A1 (130, 80) -> (129, 81) centre (129, 80) ccw
  arc A2 (111, 81) -> (110, 80) centre (111, 80) ccw
  arc A3 (110, 72) -> (111, 71) centre (111, 72) ccw
extrude "Rubber pad 4" add sketch "Rubber pad 4 outline" along normal blind 3 separate body makes body 16 in component "REFERENCE - four 20 x 10 x 3 mm rubber pads"
sketch "Camera carrier outline" plane through (0, 0, 0) normal (0, 0, 1) x (1, 0, 0) in component "04 Camera G carrier - PRINT"
  line L0 (3, 0) -> (35, 0)
  line L1 (38, 3) -> (38, 35)
  line L2 (35, 38) -> (3, 38)
  line L3 (0, 35) -> (0, 3)
  arc A0 (35, 0) -> (38, 3) centre (35, 3) ccw
  arc A1 (38, 35) -> (35, 38) centre (35, 35) ccw
  arc A2 (3, 38) -> (0, 35) centre (3, 35) ccw
  arc A3 (0, 3) -> (3, 0) centre (3, 3) ccw
extrude "Camera carrier" add sketch "Camera carrier outline" along normal blind 3 separate body makes body 17 in component "04 Camera G carrier - PRINT"
ref_plane "WorkPlane1" through (0, 0, 3) normal (0, 0, 1) x (1, 0, 0) in component "04 Camera G carrier - PRINT"
sketch "Waveshare G PCB supports layout" plane through (0, 0, 3) normal (0, 0, 1) x (1, 0, 0) in component "04 Camera G carrier - PRINT"
  circle A0 centre (8.5, 14.5) radius 2.3
  circle A1 centre (29.5, 14.5) radius 2.3
  circle A2 centre (8.5, 28) radius 2.3
  circle A3 centre (29.5, 28) radius 2.3
extrude "Waveshare G PCB supports" add sketch "Waveshare G PCB supports layout" along normal blind 2.5 bodies 17 in component "04 Camera G carrier - PRINT"
sketch "M2 camera through holes - 21 x 13.5 mm layout" plane through (0, 0, 0) normal (0, 0, 1) x (1, 0, 0) in component "04 Camera G carrier - PRINT"
  circle A0 centre (8.5, 14.5) radius 1.15
  circle A1 centre (29.5, 14.5) radius 1.15
  circle A2 centre (8.5, 28) radius 1.15
  circle A3 centre (29.5, 28) radius 1.15
extrude "M2 camera through holes - 21 x 13.5 mm" cut sketch "M2 camera through holes - 21 x 13.5 mm layout" along normal blind 6 bodies 17 in component "04 Camera G carrier - PRINT"
sketch "M2 nut recesses layout" plane through (0, 0, 0) normal (0, 0, 1) x (1, 0, 0) in component "04 Camera G carrier - PRINT"
  circle A0 centre (8.5, 14.5) radius 2.35
  circle A1 centre (29.5, 14.5) radius 2.35
  circle A2 centre (8.5, 28) radius 2.35
  circle A3 centre (29.5, 28) radius 2.35
extrude "M2 nut recesses" cut sketch "M2 nut recesses layout" along normal blind 1.7 bodies 17 in component "04 Camera G carrier - PRINT"
sketch "Camera cap M2.5 clearance layout" plane through (0, 0, 0) normal (0, 0, 1) x (1, 0, 0) in component "04 Camera G carrier - PRINT"
  circle A0 centre (3.5, 3.5) radius 1.4
  circle A1 centre (34.5, 3.5) radius 1.4
  circle A2 centre (3.5, 34.5) radius 1.4
  circle A3 centre (34.5, 34.5) radius 1.4
extrude "Camera cap M2.5 clearance" cut sketch "Camera cap M2.5 clearance layout" along normal blind 3.2 bodies 17 in component "04 Camera G carrier - PRINT"
sketch "Camera bracket M3 clearance layout (2)" plane through (0, 0, 0) normal (0, 0, 1) x (1, 0, 0) in component "04 Camera G carrier - PRINT"
  circle A0 centre (3.5, 11) radius 1.7
  circle A1 centre (34.5, 11) radius 1.7
  circle A2 centre (3.5, 22) radius 1.7
  circle A3 centre (34.5, 22) radius 1.7
extrude "Camera bracket M3 clearance'" cut sketch "Camera bracket M3 clearance layout (2)" along normal blind 3.2 bodies 17 in component "04 Camera G carrier - PRINT"
ref_plane "WorkPlane1" through (0, 0, 3) normal (0, 0, 1) x (1, 0, 0) in component "05 Camera G protective cap - PRINT"
sketch "Camera cap shell outline" plane through (0, 0, 3) normal (0, 0, 1) x (1, 0, 0) in component "05 Camera G protective cap - PRINT"
  line L0 (3, 0) -> (35, 0)
  line L1 (38, 3) -> (38, 35)
  line L2 (35, 38) -> (3, 38)
  line L3 (0, 35) -> (0, 3)
  arc A0 (35, 0) -> (38, 3) centre (35, 3) ccw
  arc A1 (38, 35) -> (35, 38) centre (35, 35) ccw
  arc A2 (3, 38) -> (0, 35) centre (3, 35) ccw
  arc A3 (0, 3) -> (3, 0) centre (3, 3) ccw
extrude "Camera cap shell" add sketch "Camera cap shell outline" along normal blind 17 separate body makes body 18 in component "05 Camera G protective cap - PRINT"
ref_plane "WorkPlane2" through (0, 0, 2.9) normal (0, 0, 1) x (1, 0, 0) in component "05 Camera G protective cap - PRINT"
sketch "Camera body clearance outline" plane through (0, 0, 2.9) normal (0, 0, 1) x (1, 0, 0) in component "05 Camera G protective cap - PRINT"
  line L0 (3, 2.4) -> (35, 2.4)
  line L1 (35.6, 3) -> (35.6, 35)
  line L2 (35, 35.6) -> (3, 35.6)
  line L3 (2.4, 35) -> (2.4, 3)
  arc A0 (35, 2.4) -> (35.6, 3) centre (35, 3) ccw
  arc A1 (35.6, 35) -> (35, 35.6) centre (35, 35) ccw
  arc A2 (3, 35.6) -> (2.4, 35) centre (3, 35) ccw
  arc A3 (2.4, 3) -> (3, 2.4) centre (3, 3) ccw
extrude "Camera body clearance" cut sketch "Camera body clearance outline" along normal blind 14.7 bodies 18 in component "05 Camera G protective cap - PRINT"
ref_plane "WorkPlane3" through (0, 0, 17.5) normal (0, 0, 1) x (1, 0, 0) in component "05 Camera G protective cap - PRINT"
sketch "Fisheye clearance" plane through (0, 0, 17.5) normal (0, 0, 1) x (1, 0, 0) in component "05 Camera G protective cap - PRINT"
  circle A0 centre (19, 21.65) radius 11
  dimension "d201" = 22
  measures "d201" diameter of A0
extrude "Fisheye aperture" cut sketch "Fisheye clearance" along normal blind 3 bodies 18 in component "05 Camera G protective cap - PRINT"
ref_plane "WorkPlane4" through (0, 0, 3) normal (0, 0, 1) x (1, 0, 0) in component "05 Camera G protective cap - PRINT"
sketch "Cap screw pillars layout" plane through (0, 0, 3) normal (0, 0, 1) x (1, 0, 0) in component "05 Camera G protective cap - PRINT"
  circle A0 centre (3.5, 3.5) radius 3
  circle A1 centre (34.5, 3.5) radius 3
  circle A2 centre (3.5, 34.5) radius 3
  circle A3 centre (34.5, 34.5) radius 3
extrude "Cap screw pillars" add sketch "Cap screw pillars layout" along normal blind 14.6 bodies 18 in component "05 Camera G protective cap - PRINT"
ref_plane "WorkPlane5" through (0, 0, 2.9) normal (0, 0, 1) x (1, 0, 0) in component "05 Camera G protective cap - PRINT"
sketch "M2.5 cap pilots layout" plane through (0, 0, 2.9) normal (0, 0, 1) x (1, 0, 0) in component "05 Camera G protective cap - PRINT"
  circle A0 centre (3.5, 3.5) radius 1.05
  circle A1 centre (34.5, 3.5) radius 1.05
  circle A2 centre (3.5, 34.5) radius 1.05
  circle A3 centre (34.5, 34.5) radius 1.05
extrude "M2.5 cap pilots" cut sketch "M2.5 cap pilots layout" along normal blind 8 bodies 18 in component "05 Camera G protective cap - PRINT"
ref_plane "WorkPlane6" through (0, 0, 3) normal (0, 0, 1) x (1, 0, 0) in component "05 Camera G protective cap - PRINT"
sketch "Ribbon cable exit layout" plane through (0, 0, 3) normal (0, 0, 1) x (1, 0, 0) in component "05 Camera G protective cap - PRINT"
  line L0 (10, -1) -> (28, -1)
  line L1 (28, -1) -> (28, 3)
  line L2 (28, 3) -> (10, 3)
  line L3 (10, 3) -> (10, -1)
extrude "Ribbon cable exit" cut sketch "Ribbon cable exit layout" along normal blind 5 bodies 18 in component "05 Camera G protective cap - PRINT"
ref_plane "WorkPlane1" through (0, 0, 5.5) normal (0, 0, 1) x (1, 0, 0) in component "REFERENCE - Waveshare RPi Camera G PCB and lens"
sketch "Camera PCB 25 x 24 outline" plane through (0, 0, 5.5) normal (0, 0, 1) x (1, 0, 0) in component "REFERENCE - Waveshare RPi Camera G PCB and lens"
  line L0 (6.5, 6) -> (31.5, 6)
  line L1 (31.5, 6) -> (31.5, 30)
  line L2 (31.5, 30) -> (6.5, 30)
  line L3 (6.5, 30) -> (6.5, 6)
extrude "Camera PCB 25 x 24" add sketch "Camera PCB 25 x 24 outline" along normal blind 1.2 separate body makes body 19 in component "REFERENCE - Waveshare RPi Camera G PCB and lens"
ref_plane "WorkPlane2" through (0, 0, 5.4) normal (0, 0, 1) x (1, 0, 0) in component "REFERENCE - Waveshare RPi Camera G PCB and lens"
sketch "Camera mounting holes layout" plane through (0, 0, 5.4) normal (0, 0, 1) x (1, 0, 0) in component "REFERENCE - Waveshare RPi Camera G PCB and lens"
  circle A0 centre (8.5, 14.5) radius 1.1
  circle A1 centre (29.5, 14.5) radius 1.1
  circle A2 centre (8.5, 28) radius 1.1
  circle A3 centre (29.5, 28) radius 1.1
extrude "Camera mounting holes" cut sketch "Camera mounting holes layout" along normal blind 1.5 bodies 19 in component "REFERENCE - Waveshare RPi Camera G PCB and lens"
ref_plane "WorkPlane3" through (0, 0, 6.7) normal (0, 0, 1) x (1, 0, 0) in component "REFERENCE - Waveshare RPi Camera G PCB and lens"
sketch "Approximate fisheye barrel - verify height layout" plane through (0, 0, 6.7) normal (0, 0, 1) x (1, 0, 0) in component "REFERENCE - Waveshare RPi Camera G PCB and lens"
  circle A0 centre (19, 21.65) radius 8
extrude "Approximate fisheye barrel - verify height" add sketch "Approximate fisheye barrel - verify height layout" along normal blind 18 separate body makes body 20 in component "REFERENCE - Waveshare RPi Camera G PCB and lens"
ref_plane "WorkPlane1" through (-2, 0, 0) normal (1, 0, 0) x (0, 1, 0) in component "06 Camera 45 degree bracket - PRINT - provisional aim"
sketch "45 degree bracket section" plane through (-2, 0, 0) normal (1, 0, 0) x (0, 0, -1) in component "06 Camera 45 degree bracket - PRINT - provisional aim"
  line L0 (0.7071, 0) -> (26.7071, 26)
  line L1 (26.7071, 26) -> (0, 26)
  line L2 (0, 26) -> (0, 0)
  line L3 (0, 0) -> (0.7071, 0)
extrude "45 degree cradle" add sketch "45 degree bracket section" along normal blind 42 separate body makes body 21 in component "06 Camera 45 degree bracket - PRINT - provisional aim"
sketch "Carrier M3 pilot holes layout" plane through (0, 0, 0) normal (0, 0, 1) x (1, 0, 0) in component "06 Camera 45 degree bracket - PRINT - provisional aim"
  circle A0 centre (3.5, 11) radius 1.25
  circle A1 centre (34.5, 11) radius 1.25
  circle A2 centre (3.5, 22) radius 1.25
  circle A3 centre (34.5, 22) radius 1.25
extrude "Carrier M3 pilot holes" cut sketch "Carrier M3 pilot holes layout" against normal blind 7 bodies 21 in component "06 Camera 45 degree bracket - PRINT - provisional aim"
ref_plane "WorkPlane2" through (0, 0, -32) normal (0, 0, 1) x (1, 0, 0) in component "06 Camera 45 degree bracket - PRINT - provisional aim"
sketch "Ribbon routing channel layout" plane through (0, 0, -32) normal (0, 0, 1) x (1, 0, 0) in component "06 Camera 45 degree bracket - PRINT - provisional aim"
  line L0 (10, -1) -> (28, -1)
  line L1 (28, -1) -> (28, 14)
  line L2 (28, 14) -> (10, 14)
  line L3 (10, 14) -> (10, -1)
extrude "Ribbon routing channel" cut sketch "Ribbon routing channel layout" along normal blind 33 bodies 21 in component "06 Camera 45 degree bracket - PRINT - provisional aim"
sketch "Case mating plane references" plane through (0, 0, 0) normal (0, 0, 1) x (1, 0, 0) in component "06 Camera 45 degree bracket - PRINT - provisional aim"
  point P0 (-52, -26.5165)
  point P1 (48, -26.5165)
  point P2 (-52, 44.1942)
ref_plane "WorkPlane3" through (-52, -26.5165, 25.8094) normal (0, 0.707107, 0.707107) x (-1, 0, 0) in component "06 Camera 45 degree bracket - PRINT - provisional aim"
sketch "Case attachment - M3x6" plane through (0, -0.3536, -0.3536) normal (0, 0.707107, 0.707107) x (-1, 0, 0) in component "06 Camera 45 degree bracket - PRINT - provisional aim"
  circle A0 centre (-7, -12) radius 1.25
  circle A1 centre (-31, -12) radius 1.25
  circle A2 centre (-7, -24) radius 1.25
  circle A3 centre (-31, -24) radius 1.25
extrude "Case-side M3 pilots" cut sketch "Case attachment - M3x6" along normal blind 4.5 bodies 21 in component "06 Camera 45 degree bracket - PRINT - provisional aim"
ref_plane "WorkPlane12" through (0, 0, 40) normal (0, 0, 1) x (1, 0, 0) in component "02 Pi tray and upper shell - PRINT"
sketch "Camera ribbon entry layout" plane through (0, 0, 40) normal (0, 0, 1) x (1, 0, 0) in component "02 Pi tray and upper shell - PRINT"
  line L0 (62, -0.5) -> (80, -0.5)
  line L1 (80, -0.5) -> (80, 3)
  line L2 (80, 3) -> (62, 3)
  line L3 (62, 3) -> (62, -0.5)
extrude "Camera ribbon entry" cut sketch "Camera ribbon entry layout" along normal blind 3 bodies 2 in component "02 Pi tray and upper shell - PRINT"
sketch "Camera M2 nut and screw-tip relief layout" plane through (0, 0, 0) normal (0, 0, 1) x (1, 0, 0) in component "06 Camera 45 degree bracket - PRINT - provisional aim"
  circle A0 centre (8.5, 14.5) radius 2.6
  circle A1 centre (29.5, 14.5) radius 2.6
extrude "Camera M2 nut and screw-tip relief" cut sketch "Camera M2 nut and screw-tip relief layout" against normal blind 2 bodies 21 in component "06 Camera 45 degree bracket - PRINT - provisional aim"
sketch "Cap fastener head relief layout" plane through (0, 0, 0) normal (0, 0, 1) x (1, 0, 0) in component "06 Camera 45 degree bracket - PRINT - provisional aim"
  circle A0 centre (3.5, 3.5) radius 2.75
  circle A1 centre (34.5, 3.5) radius 2.75
extrude "Cap fastener head relief" cut sketch "Cap fastener head relief layout" against normal blind 3.2 bodies 21 in component "06 Camera 45 degree bracket - PRINT - provisional aim"
ref_plane "WorkPlane1" through (0, 0, 2) normal (0, 0, 1) x (1, 0, 0) in component "07 Doorframe mounting platform - PRINT"
sketch "Six mm platform outline" plane through (0, 0, 2) normal (0, 0, 1) x (1, 0, 0) in component "07 Doorframe mounting platform - PRINT"
  line L0 (-21, -42) -> (163, -42)
  line L1 (166, -39) -> (166, 47)
  line L2 (163, 50) -> (-21, 50)
  line L3 (-24, 47) -> (-24, -39)
  arc A0 (163, -42) -> (166, -39) centre (163, -39) ccw
  arc A1 (166, 47) -> (163, 50) centre (163, 47) ccw
  arc A2 (-21, 50) -> (-24, 47) centre (-21, 47) ccw
  arc A3 (-24, -39) -> (-21, -42) centre (-21, -39) ccw
extrude "Six mm platform" add sketch "Six mm platform outline" along normal blind 6 separate body makes body 22 in component "07 Doorframe mounting platform - PRINT"
ref_plane "WorkPlane2" through (0, 0, 1.9) normal (0, 0, 1) x (1, 0, 0) in component "07 Doorframe mounting platform - PRINT"
sketch "Platform lightening windows layout" plane through (0, 0, 1.9) normal (0, 0, 1) x (1, 0, 0) in component "07 Doorframe mounting platform - PRINT"
  line L0 (8, -17) -> (59, -17)
  line L1 (59, -17) -> (59, 27)
  line L2 (59, 27) -> (8, 27)
  line L3 (8, 27) -> (8, -17)
  line L4 (69, -17) -> (119, -17)
  line L5 (119, -17) -> (119, 27)
  line L6 (119, 27) -> (69, 27)
  line L7 (69, 27) -> (69, -17)
extrude "Platform lightening windows" cut sketch "Platform lightening windows layout" along normal blind 6.2 bodies 22 in component "07 Doorframe mounting platform - PRINT"
ref_plane "WorkPlane3" through (0, 0, 8) normal (0, 0, 1) x (1, 0, 0) in component "07 Doorframe mounting platform - PRINT"
sketch "Case hard mounting bosses layout" plane through (0, 0, 8) normal (0, 0, 1) x (1, 0, 0) in component "07 Doorframe mounting platform - PRINT"
  circle A0 centre (132, -14) radius 5
  circle A1 centre (132, 22) radius 5
extrude "Case hard mounting bosses" add sketch "Case hard mounting bosses layout" along normal blind 2.2 bodies 22 in component "07 Doorframe mounting platform - PRINT"
ref_plane "WorkPlane4" through (0, 0, 1.9) normal (0, 0, 1) x (1, 0, 0) in component "07 Doorframe mounting platform - PRINT"
sketch "Case M4 clearance layout" plane through (0, 0, 1.9) normal (0, 0, 1) x (1, 0, 0) in component "07 Doorframe mounting platform - PRINT"
  circle A0 centre (132, -14) radius 2.25
  circle A1 centre (132, 22) radius 2.25
extrude "Case M4 clearance" cut sketch "Case M4 clearance layout" along normal blind 8.4 bodies 22 in component "07 Doorframe mounting platform - PRINT"
ref_plane "WorkPlane5" through (0, 0, 3) normal (0, 0, 1) x (1, 0, 0) in component "07 Doorframe mounting platform - PRINT"
sketch "Side-load M4 captive nut channels layout" plane through (0, 0, 3) normal (0, 0, 1) x (1, 0, 0) in component "07 Doorframe mounting platform - PRINT"
  line L0 (127.8, -17.6) -> (167, -17.6)
  line L1 (167, -17.6) -> (167, -10.4)
  line L2 (167, -10.4) -> (127.8, -10.4)
  line L3 (127.8, -10.4) -> (127.8, -17.6)
  line L4 (127.8, 18.4) -> (167, 18.4)
  line L5 (167, 18.4) -> (167, 25.6)
  line L6 (167, 25.6) -> (127.8, 25.6)
  line L7 (127.8, 25.6) -> (127.8, 18.4)
extrude "Side-load M4 captive nut channels" cut sketch "Side-load M4 captive nut channels layout" along normal blind 3.4 bodies 22 in component "07 Doorframe mounting platform - PRINT"
ref_plane "WorkPlane6" through (0, 0, 8) normal (0, 0, 1) x (1, 0, 0) in component "07 Doorframe mounting platform - PRINT"
sketch "Case locating tab 1 outline" plane through (0, 0, 8) normal (0, 0, 1) x (1, 0, 0) in component "07 Doorframe mounting platform - PRINT"
  line L0 (10, 48.6) -> (30, 48.6)
  line L1 (30, 48.6) -> (30, 50)
  line L2 (30, 50) -> (10, 50)
  line L3 (10, 50) -> (10, 48.6)
extrude "Case locating tab 1" add sketch "Case locating tab 1 outline" along normal blind 6 bodies 22 in component "07 Doorframe mounting platform - PRINT"